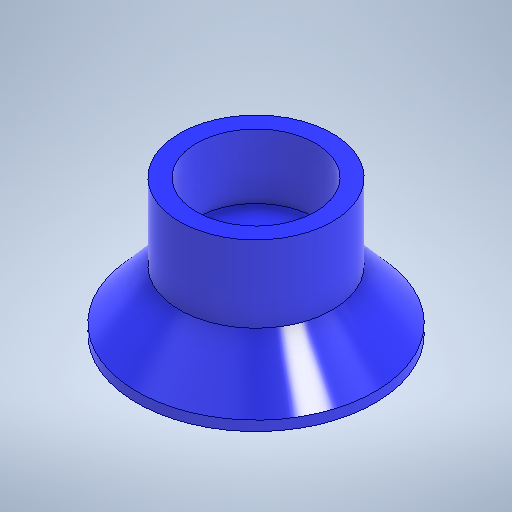
# Autodesk Inventor part: Резиновый наконечник
Saved by Autodesk Inventor 2025.1 (Build 291241000, 241)
## iProperties
Created: 2026-10-22
Part Number: Резиновый наконечник
Material: Резина
Document SubType Name: Modeling
Designer: Ваня
Density: 0.93 g/cm^3
Appearance: Синий — малярная краска — глянцевая
Author: Ваня
Autodesk Inventor part; units mm, degrees
ref_plane "YZ Plane" through (0, 0, 0) normal (1, 0, 0) x (0, 1, 0)
ref_plane "XZ Plane" through (0, 0, 0) normal (0, 1, 0) x (-1, 0, 0)
ref_plane "XY Plane" through (0, 0, 0) normal (0, 0, 1) x (1, 0, 0)
sketch "Эскиз4" plane through (0, 0, 0) normal (0, 0, 1) x (1, 0, 0)
  line L0 (0, 0) -> (0, 8)
  line L1 (0, 0) -> (7.5, 0)
  line L2 (0, 0) -> (0, 3.5)
  line L3 (0, 3.5) -> (4.5, 3.5)
  line L4 (4.5, 3.5) -> (4.5, 8)
  line L5 (4.5, 8) -> (0, 8)
  line L6 (4.5, 3.5) -> (7.5, 0)
  line L7 (0, 3.5) -> (3.85, 3.5)
  line L8 (7.5, 0) -> (7, 0)
  line L9 (7, 0) -> (3.85, 3.5)
  line L10 (0, 0) -> (0, 20)
  dimension "d14" = 8
  dimension "d15" = 7.5
  dimension "d16" = 3.5
  dimension "d17" = 4.5
  dimension "d18" = 3.85
  dimension "d19" = 0.5
  dimension "d20" = 20
  constraints: 22 end point, 4 point on line, 3 perpendicular, 1 horizontal, 1 vertical
  measures "d14" distance of L0.start L0.end
  measures "d15" distance of L0.start L1.end
  measures "d16" distance of L0.start L2.end
  measures "d17" distance of L2.end L3.end
  measures "d18" distance of L2.end L7.end
  measures "d19" distance of L1.end L8.end
  measures "d20" distance of L0.start L10.end
revolve "Вращение2" add sketch "Эскиз4" angle 360 about axis through (0, 0, 0) along (0, 1, 0) contours L0 L5 L4 L3 | L9 L3 L6 L1
sketch "Эскиз5" plane through (0, 0, 0) normal (1, 0, 0) x (0, 1, 0)
  line L0 (3.5, -3.85) -> (0, -7) projected
  line L1 (3.5, -3.85) -> (3.5, -3.35)
  line L2 (3.5, -4.5) -> (3.5, 4.5) projected
  circle A0 centre (3.5, -3.35) radius 0.5
  line L3 (3.5, 0) -> (-6.5, 0)
  point P0 (0, 0)
  point P1 (3.5, -2.85)
  dimension "d22" = 0.5
  dimension "d23" = 10
  constraints: 4 end point, 2 point on line, 1 coincident, 1 horizontal, 1 midpoint, 3 other
  measures "d22" distance of L1.start L1.end
  measures "d23" distance of L3.start L3.end
revolve "Вращение3" add sketch "Эскиз5" angle 360 about axis through (0, 3.5, 0) along (0, -1, 0) picked at (3.4601, -3.6785) contours A0 L2 L1
sketch "Эскиз6" plane through (0, 3.5, 0) normal (0, -1, 0) x (1, 0, 0)
  circle A0 centre (0, 0) radius 2.85 projected
  line L0 (2.85, 0) -> (3.85, 0)
  circle A1 centre (0, 0) radius 3.85 projected
  line L1 (3.85, 0) -> (3.85, 0.5)
  line L2 (3.85, 0.5) -> (2.35, 0.5)
  line L3 (2.35, 0.5) -> (2.35, -0.5)
  line L4 (2.35, -0.5) -> (3.85, -0.5)
  line L5 (3.85, -0.5) -> (3.85, 0)
  line L6 (0, 0) -> (0, -1)
  circle A2 centre (0, 0) radius 3.85
  line L7 (-3.85, 0.5) -> (-2.35, 0.5)
  line L8 (-2.35, 0.5) -> (-2.35, -0.5)
  line L9 (-2.35, -0.5) -> (-3.85, -0.5)
  point P0 (-3.8174, -0.5)
  point P1 (-3.8174, 0.5)
  point P2 (3.8174, -0.5)
  point P3 (3.8174, 0.5)
  dimension "d25" = 0.5
  dimension "d26" = 1.5
  dimension "d27" = 1
  dimension "d28" = 1
  constraints: 20 end point, 5 perpendicular, 4 symmetric about line, 1 centre point, 1 horizontal alignment, 1 line through centre, 1 point on line, 1 vertical, 3 other
  measures "d25" distance of L0.end L1.end
  measures "d26" distance of L1.end L2.end
  measures "d27" distance of L2.end L3.end
  measures "d28" distance of L6.start L6.end
extrude "Выдавливание3" cut sketch "Эскиз6" along normal blind 10 contours A0 L4 L3 L2 | L0 A1 L4 A0 | A0 L2 A1 L0 | L7 L8 L9 A0 | A0 L9 A1 L7
sketch "Эскиз7" plane through (2.8058, 3.5, -0.5) normal (0, -1, 0) x (1, 0, 0)
  circle A0 centre (-2.8058, 0.5) radius 1.5
  dimension "d31" = 3
  constraints: 1 centre point, 1 coincident
  measures "d31" diameter of A0
extrude "Выдавливание4" cut sketch "Эскиз7" against normal blind 10
sketch "Эскиз8" plane through (0, 0, 0) normal (1, 0, 0) x (0, 1, 0)
  line L0 (3.5, -3.85) -> (0, -7) projected
  line L1 (0, -7) -> (0.5833, -7)
  line L2 (0, -7.5) -> (3.5, -4.5) projected
  line L3 (0, -7.5) -> (0, 7.5) projected
  line L4 (0, -7) -> (0, -7.5)
  line L5 (0, -7.5) -> (0.5833, -7)
  line L6 (0, 0) -> (-10, 0)
  dimension "d34" = 10
  constraints: 8 end point, 2 point on line, 1 collinear, 1 horizontal, 1 perpendicular
  measures "d34" distance of L6.start L6.end
revolve "Вращение4" cut sketch "Эскиз8" angle 360 about axis through (0, 0, 0) along (0, -1, 0)
sketch "Эскиз9" plane through (0, 8, 0) normal (0, 1, 0) x (1, 0, 0)
  circle A0 centre (0, 0) radius 3.5
  dimension "d36" = 7
  constraints: 1 centre point, 1 coincident
  measures "d36" diameter of A0
extrude "Выдавливание5" cut sketch "Эскиз9" against normal blind 3.8
